Autodesk Fusion 360 part; units mm, degrees
(part 2 of 2)
ref_plane "WorkPlane1" through (0, 0, 12) normal (0, 0, 1) x (1, 0, 0) in component "E01 MSP3525 no-touch PCB - verify supplied variant"
sketch "MSP3525 family PCB outline" plane through (0, 0, 12) normal (0, 0, 1) x (1, 0, 0) in component "E01 MSP3525 no-touch PCB - verify supplied variant"
  line L0 (19.54, 93.25) -> (117.54, 93.25)
  line L1 (117.54, 93.25) -> (117.54, 148.75)
  line L2 (117.54, 148.75) -> (19.54, 148.75)
  line L3 (19.54, 148.75) -> (19.54, 93.25)
extrude "MSP3525 family PCB outline (1)" add sketch "MSP3525 family PCB outline" along normal blind 1.6 separate body makes body 7 in component "E01 MSP3525 no-touch PCB - verify supplied variant"
ref_plane "WorkPlane2" through (0, 0, 12) normal (0, 0, 1) x (1, 0, 0) in component "E01 MSP3525 no-touch PCB - verify supplied variant"
sketch "Family drawing 3.2mm fixing" plane through (0, 0, 12) normal (0, 0, 1) x (1, 0, 0) in component "E01 MSP3525 no-touch PCB - verify supplied variant"
  circle A0 centre (22.54, 96.25) radius 1.6
extrude "Family drawing 3.2mm fixing (1)" cut sketch "Family drawing 3.2mm fixing" along normal blind 1.6 bodies 7 in component "E01 MSP3525 no-touch PCB - verify supplied variant"
ref_plane "WorkPlane3" through (0, 0, 12) normal (0, 0, 1) x (1, 0, 0) in component "E01 MSP3525 no-touch PCB - verify supplied variant"
sketch "Family drawing 3.2mm fixing (1)" plane through (0, 0, 12) normal (0, 0, 1) x (1, 0, 0) in component "E01 MSP3525 no-touch PCB - verify supplied variant"
  circle A0 centre (22.54, 145.75) radius 1.6
extrude "Family drawing 3.2mm fixing (2)" cut sketch "Family drawing 3.2mm fixing (1)" along normal blind 1.6 bodies 7 in component "E01 MSP3525 no-touch PCB - verify supplied variant"
ref_plane "WorkPlane4" through (0, 0, 12) normal (0, 0, 1) x (1, 0, 0) in component "E01 MSP3525 no-touch PCB - verify supplied variant"
sketch "Family drawing 3.2mm fixing (2)" plane through (0, 0, 12) normal (0, 0, 1) x (1, 0, 0) in component "E01 MSP3525 no-touch PCB - verify supplied variant"
  circle A0 centre (114.54, 96.25) radius 1.6
extrude "Family drawing 3.2mm fixing (3)" cut sketch "Family drawing 3.2mm fixing (2)" along normal blind 1.6 bodies 7 in component "E01 MSP3525 no-touch PCB - verify supplied variant"
ref_plane "WorkPlane5" through (0, 0, 12) normal (0, 0, 1) x (1, 0, 0) in component "E01 MSP3525 no-touch PCB - verify supplied variant"
sketch "Family drawing 3.2mm fixing (3)" plane through (0, 0, 12) normal (0, 0, 1) x (1, 0, 0) in component "E01 MSP3525 no-touch PCB - verify supplied variant"
  circle A0 centre (114.54, 145.75) radius 1.6
extrude "Family drawing 3.2mm fixing (4)" cut sketch "Family drawing 3.2mm fixing (3)" along normal blind 1.6 bodies 7 in component "E01 MSP3525 no-touch PCB - verify supplied variant"
ref_plane "WorkPlane1" through (0, 0, 9) normal (0, 0, 1) x (1, 0, 0) in component "E02 MSP3525 LCD glass - nominal stack"
sketch "LCD and adhesive envelope" plane through (0, 0, 9) normal (0, 0, 1) x (1, 0, 0) in component "E02 MSP3525 LCD glass - nominal stack"
  line L0 (26.08, 93.25) -> (111.04, 93.25)
  line L1 (111.04, 93.25) -> (111.04, 148.75)
  line L2 (111.04, 148.75) -> (26.08, 148.75)
  line L3 (26.08, 148.75) -> (26.08, 93.25)
extrude "LCD and adhesive envelope (1)" add sketch "LCD and adhesive envelope" along normal blind 3 separate body makes body 8 in component "E02 MSP3525 LCD glass - nominal stack"
ref_plane "WorkPlane1" through (0, 0, 8.9) normal (0, 0, 1) x (1, 0, 0) in component "REF Green active area 480x320"
sketch "Active area - align physically" plane through (0, 0, 8.9) normal (0, 0, 1) x (1, 0, 0) in component "REF Green active area 480x320"
  line L0 (30.78, 96.52) -> (104.22, 96.52)
  line L1 (104.22, 96.52) -> (104.22, 145.48)
  line L2 (104.22, 145.48) -> (30.78, 145.48)
  line L3 (30.78, 145.48) -> (30.78, 96.52)
extrude "Active area - align physically (1)" add sketch "Active area - align physically" along normal blind 0.1 separate body makes body 9 in component "REF Green active area 480x320"
ref_plane "WorkPlane1" through (0, 0, 13.6) normal (0, 0, 1) x (1, 0, 0) in component "E03 Display header and rear components - keepouts"
sketch "14-pin header clearance to total 14.3mm" plane through (0, 0, 13.6) normal (0, 0, 1) x (1, 0, 0) in component "E03 Display header and rear components - keepouts"
  line L0 (20.3, 103.24) -> (22.84, 103.24)
  line L1 (22.84, 103.24) -> (22.84, 138.8)
  line L2 (22.84, 138.8) -> (20.3, 138.8)
  line L3 (20.3, 138.8) -> (20.3, 103.24)
extrude "14-pin header clearance to total 14.3mm (1)" add sketch "14-pin header clearance to total 14.3mm" along normal blind 9.7 separate body makes body 10 in component "E03 Display header and rear components - keepouts"
ref_plane "WorkPlane2" through (0, 0, 13.6) normal (0, 0, 1) x (1, 0, 0) in component "E03 Display header and rear components - keepouts"
sketch "SD socket and components envelope - unused" plane through (0, 0, 13.6) normal (0, 0, 1) x (1, 0, 0) in component "E03 Display header and rear components - keepouts"
  line L0 (91, 114) -> (113, 114)
  line L1 (113, 114) -> (113, 132)
  line L2 (113, 132) -> (91, 132)
  line L3 (91, 132) -> (91, 114)
extrude "SD socket and components envelope - unused (1)" add sketch "SD socket and components envelope - unused" along normal blind 3 separate body makes body 11 in component "E03 Display header and rear components - keepouts"
ref_plane "WorkPlane1" through (0, 0, -16) normal (0, 0, 1) x (1, 0, 0) in component "REF Select push knob"
sketch "Purchased 22mm knob" plane through (0, 0, -16) normal (0, 0, 1) x (1, 0, 0) in component "REF Select push knob"
  circle A0 centre (36, 36) radius 11
extrude "Purchased 22mm knob (1)" add sketch "Purchased 22mm knob" along normal blind 13 separate body makes body 12 in component "REF Select push knob"
ref_plane "WorkPlane1" through (0, 0, -16) normal (0, 0, 1) x (1, 0, 0) in component "REF Intensity knob"
sketch "Purchased 22mm knob (2)" plane through (0, 0, -16) normal (0, 0, 1) x (1, 0, 0) in component "REF Intensity knob"
  circle A0 centre (99, 36) radius 11
extrude "Purchased 22mm knob (1)'" add sketch "Purchased 22mm knob (2)" along normal blind 13 separate body makes body 13 in component "REF Intensity knob"
ref_plane "WorkPlane1" through (0, 0, -2) normal (0, 0, 1) x (1, 0, 0) in component "REF HOLD toggle"
sketch "Toggle washer" plane through (0, 0, -2) normal (0, 0, 1) x (1, 0, 0) in component "REF HOLD toggle"
  circle A0 centre (18, 70) radius 4
extrude "Toggle washer (1)" add sketch "Toggle washer" along normal blind 2 separate body makes body 14 in component "REF HOLD toggle"
ref_plane "WorkPlane2" through (0, 0, -15) normal (0, 0, 1) x (1, 0, 0) in component "REF HOLD toggle"
sketch "Toggle lever" plane through (0, 0, -15) normal (0, 0, 1) x (1, 0, 0) in component "REF HOLD toggle"
  circle A0 centre (18, 70) radius 1.5
extrude "Toggle lever (1)" add sketch "Toggle lever" along normal blind 13 separate body makes body 15 in component "REF HOLD toggle"
ref_plane "WorkPlane3" through (0, 0, 3) normal (0, 0, 1) x (1, 0, 0) in component "REF HOLD toggle"
sketch "Switch body" plane through (0, 0, 3) normal (0, 0, 1) x (1, 0, 0) in component "REF HOLD toggle"
  line L0 (13, 64) -> (23, 64)
  line L1 (23, 64) -> (23, 76)
  line L2 (23, 76) -> (13, 76)
  line L3 (13, 76) -> (13, 64)
extrude "Switch body (1)" add sketch "Switch body" along normal blind 17 separate body makes body 16 in component "REF HOLD toggle"
ref_plane "WorkPlane1" through (0, 0, -2) normal (0, 0, 1) x (1, 0, 0) in component "REF GRID toggle"
sketch "Toggle washer (2)" plane through (0, 0, -2) normal (0, 0, 1) x (1, 0, 0) in component "REF GRID toggle"
  circle A0 centre (117, 70) radius 4
extrude "Toggle washer (1)'" add sketch "Toggle washer (2)" along normal blind 2 separate body makes body 17 in component "REF GRID toggle"
ref_plane "WorkPlane2" through (0, 0, -15) normal (0, 0, 1) x (1, 0, 0) in component "REF GRID toggle"
sketch "Toggle lever (2)" plane through (0, 0, -15) normal (0, 0, 1) x (1, 0, 0) in component "REF GRID toggle"
  circle A0 centre (117, 70) radius 1.5
extrude "Toggle lever (1)'" add sketch "Toggle lever (2)" along normal blind 13 separate body makes body 18 in component "REF GRID toggle"
ref_plane "WorkPlane3" through (0, 0, 3) normal (0, 0, 1) x (1, 0, 0) in component "REF GRID toggle"
sketch "Switch body (2)" plane through (0, 0, 3) normal (0, 0, 1) x (1, 0, 0) in component "REF GRID toggle"
  line L0 (112, 64) -> (122, 64)
  line L1 (122, 64) -> (122, 76)
  line L2 (122, 76) -> (112, 76)
  line L3 (112, 76) -> (112, 64)
extrude "Switch body (1)'" add sketch "Switch body (2)" along normal blind 17 separate body makes body 19 in component "REF GRID toggle"
ref_plane "WorkPlane1" through (0, 0, 3) normal (0, 0, 1) x (1, 0, 0) in component "E04 EC11 push encoder - generic envelope"
sketch "Encoder body" plane through (0, 0, 3) normal (0, 0, 1) x (1, 0, 0) in component "E04 EC11 push encoder - generic envelope"
  line L0 (29.5, 29.5) -> (42.5, 29.5)
  line L1 (42.5, 29.5) -> (42.5, 42.5)
  line L2 (42.5, 42.5) -> (29.5, 42.5)
  line L3 (29.5, 42.5) -> (29.5, 29.5)
extrude "Encoder body (1)" add sketch "Encoder body" along normal blind 17 separate body makes body 20 in component "E04 EC11 push encoder - generic envelope"
ref_plane "WorkPlane1" through (0, 0, 3) normal (0, 0, 1) x (1, 0, 0) in component "E05 B10K pot - generic envelope"
sketch "Pot body" plane through (0, 0, 3) normal (0, 0, 1) x (1, 0, 0) in component "E05 B10K pot - generic envelope"
  circle A0 centre (99, 36) radius 8.5
extrude "Pot body (1)" add sketch "Pot body" along normal blind 17 separate body makes body 21 in component "E05 B10K pot - generic envelope"
ref_plane "WorkPlane1" through (0, 0, 64) normal (0, 0, 1) x (1, 0, 0) in component "E06 ESP32-S3 44-pin N8R8 - provisional fit envelope"
sketch "DevKit PCB - verify clone outline" plane through (0, 0, 64) normal (0, 0, 1) x (1, 0, 0) in component "E06 ESP32-S3 44-pin N8R8 - provisional fit envelope"
  line L0 (40, 20) -> (102.5, 20)
  line L1 (102.5, 20) -> (102.5, 45.4)
  line L2 (102.5, 45.4) -> (40, 45.4)
  line L3 (40, 45.4) -> (40, 20)
extrude "DevKit PCB - verify clone outline (1)" add sketch "DevKit PCB - verify clone outline" along normal blind 1.6 separate body makes body 22 in component "E06 ESP32-S3 44-pin N8R8 - provisional fit envelope"
ref_plane "WorkPlane2" through (0, 0, 65.6) normal (0, 0, 1) x (1, 0, 0) in component "E06 ESP32-S3 44-pin N8R8 - provisional fit envelope"
sketch "ESP module envelope" plane through (0, 0, 65.6) normal (0, 0, 1) x (1, 0, 0) in component "E06 ESP32-S3 44-pin N8R8 - provisional fit envelope"
  line L0 (70, 23.7) -> (90, 23.7)
  line L1 (90, 23.7) -> (90, 41.7)
  line L2 (90, 41.7) -> (70, 41.7)
  line L3 (70, 41.7) -> (70, 23.7)
extrude "ESP module envelope (1)" add sketch "ESP module envelope" along normal blind 3.4 separate body makes body 23 in component "E06 ESP32-S3 44-pin N8R8 - provisional fit envelope"
ref_plane "WorkPlane3" through (0, 0, 65.6) normal (0, 0, 1) x (1, 0, 0) in component "E06 ESP32-S3 44-pin N8R8 - provisional fit envelope"
sketch "USB connector envelope" plane through (0, 0, 65.6) normal (0, 0, 1) x (1, 0, 0) in component "E06 ESP32-S3 44-pin N8R8 - provisional fit envelope"
  line L0 (40, 22) -> (47, 22)
  line L1 (47, 22) -> (47, 30)
  line L2 (47, 30) -> (40, 30)
  line L3 (40, 30) -> (40, 22)
extrude "USB connector envelope (1)" add sketch "USB connector envelope" along normal blind 4 separate body makes body 24 in component "E06 ESP32-S3 44-pin N8R8 - provisional fit envelope"
ref_plane "WorkPlane4" through (0, 0, 65.6) normal (0, 0, 1) x (1, 0, 0) in component "E06 ESP32-S3 44-pin N8R8 - provisional fit envelope"
sketch "USB connector envelope (1)" plane through (0, 0, 65.6) normal (0, 0, 1) x (1, 0, 0) in component "E06 ESP32-S3 44-pin N8R8 - provisional fit envelope"
  line L0 (40, 35) -> (47, 35)
  line L1 (47, 35) -> (47, 43)
  line L2 (47, 43) -> (40, 43)
  line L3 (40, 43) -> (40, 35)
extrude "USB connector envelope (2)" add sketch "USB connector envelope (1)" along normal blind 4 separate body makes body 25 in component "E06 ESP32-S3 44-pin N8R8 - provisional fit envelope"
ref_plane "WorkPlane5" through (0, 0, 59) normal (0, 0, 1) x (1, 0, 0) in component "E06 ESP32-S3 44-pin N8R8 - provisional fit envelope"
sketch "Soldered pin header envelope" plane through (0, 0, 59) normal (0, 0, 1) x (1, 0, 0) in component "E06 ESP32-S3 44-pin N8R8 - provisional fit envelope"
  line L0 (43, 20) -> (98.88, 20)
  line L1 (98.88, 20) -> (98.88, 22.5)
  line L2 (98.88, 22.5) -> (43, 22.5)
  line L3 (43, 22.5) -> (43, 20)
extrude "Soldered pin header envelope (1)" add sketch "Soldered pin header envelope" along normal blind 5 separate body makes body 26 in component "E06 ESP32-S3 44-pin N8R8 - provisional fit envelope"
ref_plane "WorkPlane6" through (0, 0, 59) normal (0, 0, 1) x (1, 0, 0) in component "E06 ESP32-S3 44-pin N8R8 - provisional fit envelope"
sketch "Soldered pin header envelope (1)" plane through (0, 0, 59) normal (0, 0, 1) x (1, 0, 0) in component "E06 ESP32-S3 44-pin N8R8 - provisional fit envelope"
  line L0 (43, 42.86) -> (98.88, 42.86)
  line L1 (98.88, 42.86) -> (98.88, 45.36)
  line L2 (98.88, 45.36) -> (43, 45.36)
  line L3 (43, 45.36) -> (43, 42.86)
extrude "Soldered pin header envelope (2)" add sketch "Soldered pin header envelope (1)" along normal blind 5 separate body makes body 27 in component "E06 ESP32-S3 44-pin N8R8 - provisional fit envelope"
ref_plane "WorkPlane1" through (0, 0, 32) normal (0, 0, 1) x (1, 0, 0) in component "W01 Display and control harness corridor"
sketch "SPI service corridor" plane through (0, 0, 32) normal (0, 0, 1) x (1, 0, 0) in component "W01 Display and control harness corridor"
  line L0 (23, 40) -> (26, 40)
  line L1 (26, 40) -> (26, 125)
  line L2 (26, 125) -> (23, 125)
  line L3 (23, 125) -> (23, 40)
extrude "SPI service corridor (1)" add sketch "SPI service corridor" along normal blind 3 separate body makes body 28 in component "W01 Display and control harness corridor"
ref_plane "WorkPlane2" through (0, 0, 23.3) normal (0, 0, 1) x (1, 0, 0) in component "W01 Display and control harness corridor"
sketch "Display connector approach" plane through (0, 0, 23.3) normal (0, 0, 1) x (1, 0, 0) in component "W01 Display and control harness corridor"
  line L0 (23, 110) -> (26, 110)
  line L1 (26, 110) -> (26, 113)
  line L2 (26, 113) -> (23, 113)
  line L3 (23, 113) -> (23, 110)
extrude "Display connector approach (1)" add sketch "Display connector approach" along normal blind 8.7 separate body makes body 29 in component "W01 Display and control harness corridor"
ref_plane "WorkPlane1" through (0, 0, 65.6) normal (0, 0, 1) x (1, 0, 0) in component "W02 Single USB data power cable corridor"
sketch "USB-C plug and boot - confirm cable" plane through (0, 0, 65.6) normal (0, 0, 1) x (1, 0, 0) in component "W02 Single USB data power cable corridor"
  line L0 (15, 35) -> (40, 35)
  line L1 (40, 35) -> (40, 43)
  line L2 (40, 43) -> (15, 43)
  line L3 (15, 43) -> (15, 35)
extrude "USB-C plug and boot - confirm cable (1)" add sketch "USB-C plug and boot - confirm cable" along normal blind 7 separate body makes body 30 in component "W02 Single USB data power cable corridor"
ref_plane "WorkPlane2" through (0, 0, 73) normal (0, 0, 1) x (1, 0, 0) in component "W02 Single USB data power cable corridor"
sketch "Rear cable service loop" plane through (0, 0, 73) normal (0, 0, 1) x (1, 0, 0) in component "W02 Single USB data power cable corridor"
  line L0 (16, 28) -> (21, 28)
  line L1 (21, 28) -> (21, 36)
  line L2 (21, 36) -> (16, 36)
  line L3 (16, 36) -> (16, 28)
extrude "Rear cable service loop (1)" add sketch "Rear cable service loop" along normal blind 19 separate body makes body 31 in component "W02 Single USB data power cable corridor"
ref_plane "WorkPlane1" through (0, 0, 63) normal (0, 0, 1) x (1, 0, 0) in component "H01 Soft pads and two controller ties"
sketch "Insulating foam pad" plane through (0, 0, 63) normal (0, 0, 1) x (1, 0, 0) in component "H01 Soft pads and two controller ties"
  line L0 (46, 27) -> (50, 27)
  line L1 (50, 27) -> (50, 31)
  line L2 (50, 31) -> (46, 31)
  line L3 (46, 31) -> (46, 27)
extrude "Insulating foam pad (1)" add sketch "Insulating foam pad" along normal blind 1 separate body makes body 32 in component "H01 Soft pads and two controller ties"
ref_plane "WorkPlane2" through (0, 0, 63) normal (0, 0, 1) x (1, 0, 0) in component "H01 Soft pads and two controller ties"
sketch "Insulating foam pad (1)" plane through (0, 0, 63) normal (0, 0, 1) x (1, 0, 0) in component "H01 Soft pads and two controller ties"
  line L0 (46, 36) -> (50, 36)
  line L1 (50, 36) -> (50, 40)
  line L2 (50, 40) -> (46, 40)
  line L3 (46, 40) -> (46, 36)
extrude "Insulating foam pad (2)" add sketch "Insulating foam pad (1)" along normal blind 1 separate body makes body 33 in component "H01 Soft pads and two controller ties"
ref_plane "WorkPlane3" through (0, 0, 70) normal (0, 0, 1) x (1, 0, 0) in component "H01 Soft pads and two controller ties"
sketch "Loose tie reference - route over clear PCB" plane through (0, 0, 70) normal (0, 0, 1) x (1, 0, 0) in component "H01 Soft pads and two controller ties"
  line L0 (46, 16) -> (49, 16)
  line L1 (49, 16) -> (49, 49)
  line L2 (49, 49) -> (46, 49)
  line L3 (46, 49) -> (46, 16)
extrude "Loose tie reference - route over clear PCB (1)" add sketch "Loose tie reference - route over clear PCB" along normal blind 1 separate body makes body 34 in component "H01 Soft pads and two controller ties"
ref_plane "WorkPlane4" through (0, 0, 63) normal (0, 0, 1) x (1, 0, 0) in component "H01 Soft pads and two controller ties"
sketch "Insulating foam pad (2)" plane through (0, 0, 63) normal (0, 0, 1) x (1, 0, 0) in component "H01 Soft pads and two controller ties"
  line L0 (78, 27) -> (82, 27)
  line L1 (82, 27) -> (82, 31)
  line L2 (82, 31) -> (78, 31)
  line L3 (78, 31) -> (78, 27)
extrude "Insulating foam pad (3)" add sketch "Insulating foam pad (2)" along normal blind 1 separate body makes body 35 in component "H01 Soft pads and two controller ties"
ref_plane "WorkPlane5" through (0, 0, 63) normal (0, 0, 1) x (1, 0, 0) in component "H01 Soft pads and two controller ties"
sketch "Insulating foam pad (3)" plane through (0, 0, 63) normal (0, 0, 1) x (1, 0, 0) in component "H01 Soft pads and two controller ties"
  line L0 (78, 36) -> (82, 36)
  line L1 (82, 36) -> (82, 40)
  line L2 (82, 40) -> (78, 40)
  line L3 (78, 40) -> (78, 36)
extrude "Insulating foam pad (4)" add sketch "Insulating foam pad (3)" along normal blind 1 separate body makes body 36 in component "H01 Soft pads and two controller ties"
ref_plane "WorkPlane6" through (0, 0, 70) normal (0, 0, 1) x (1, 0, 0) in component "H01 Soft pads and two controller ties"
sketch "Loose tie reference - route over clear PCB (1)" plane through (0, 0, 70) normal (0, 0, 1) x (1, 0, 0) in component "H01 Soft pads and two controller ties"
  line L0 (78, 16) -> (81, 16)
  line L1 (81, 16) -> (81, 49)
  line L2 (81, 49) -> (78, 49)
  line L3 (78, 49) -> (78, 16)
extrude "Loose tie reference - route over clear PCB (2)" add sketch "Loose tie reference - route over clear PCB (1)" along normal blind 1 separate body makes body 37 in component "H01 Soft pads and two controller ties"
ref_plane "WorkPlane3" through (0, 0, 65.6) normal (0, 0, 1) x (1, 0, 0) in component "W02 Single USB data power cable corridor"
sketch "USB-C full boot clearance" plane through (0, 0, 65.6) normal (0, 0, 1) x (1, 0, 0) in component "W02 Single USB data power cable corridor"
  line L0 (15, 33) -> (40, 33)
  line L1 (40, 33) -> (40, 45)
  line L2 (40, 45) -> (15, 45)
  line L3 (15, 45) -> (15, 33)
extrude "USB-C full boot clearance (1)" add sketch "USB-C full boot clearance" along normal blind 8 bodies 30 31 in component "W02 Single USB data power cable corridor"
component "01 Ivory front panel" placed x (1, 0, 0) y (0, 1, 0) z (0, 0, 1) at (0, 0, 0)
component "02 Ivory shell" placed x (1, 0, 0) y (0, 1, 0) z (0, 0, 1) at (0, 0, 0)
component "03 Ivory USB rear cover" placed x (1, 0, 0) y (0, 1, 0) z (0, 0, 1) at (0, 0, 0)
component "04 Charcoal landscape bezel" placed x (1, 0, 0) y (0, 1, 0) z (0, 0, 1) at (0, 0, 0)
component "05 Replaceable MSP3525 display carrier" placed x (1, 0, 0) y (0, 1, 0) z (0, 0, 1) at (0, 0, 0)
component "06 ESP32 USB tray" placed x (1, 0, 0) y (0, 1, 0) z (0, 0, 1) at (0, 0, 0)
component "E01 MSP3525 no-touch PCB - verify supplied variant" placed x (1, 0, 0) y (0, 1, 0) z (0, 0, 1) at (0, 0, 0)
component "E02 MSP3525 LCD glass - nominal stack" placed x (1, 0, 0) y (0, 1, 0) z (0, 0, 1) at (0, 0, 0)
component "REF Green active area 480x320" placed x (1, 0, 0) y (0, 1, 0) z (0, 0, 1) at (0, 0, 0)
component "E03 Display header and rear components - keepouts" placed x (1, 0, 0) y (0, 1, 0) z (0, 0, 1) at (0, 0, 0)
component "REF Select push knob" placed x (1, 0, 0) y (0, 1, 0) z (0, 0, 1) at (0, 0, 0)
component "REF Intensity knob" placed x (1, 0, 0) y (0, 1, 0) z (0, 0, 1) at (0, 0, 0)
component "REF HOLD toggle" placed x (1, 0, 0) y (0, 1, 0) z (0, 0, 1) at (0, 0, 0)
component "REF GRID toggle" placed x (1, 0, 0) y (0, 1, 0) z (0, 0, 1) at (0, 0, 0)
component "E04 EC11 push encoder - generic envelope" placed x (1, 0, 0) y (0, 1, 0) z (0, 0, 1) at (0, 0, 0)
component "E05 B10K pot - generic envelope" placed x (1, 0, 0) y (0, 1, 0) z (0, 0, 1) at (0, 0, 0)
component "E06 ESP32-S3 44-pin N8R8 - provisional fit envelope" placed x (1, 0, 0) y (0, 1, 0) z (0, 0, 1) at (0, 0, 0)
component "W01 Display and control harness corridor" placed x (1, 0, 0) y (0, 1, 0) z (0, 0, 1) at (0, 0, 0)
component "W02 Single USB data power cable corridor" placed x (1, 0, 0) y (0, 1, 0) z (0, 0, 1) at (0, 0, 0)
component "H01 Soft pads and two controller ties" placed x (1, 0, 0) y (0, 1, 0) z (0, 0, 1) at (0, 0, 0)
